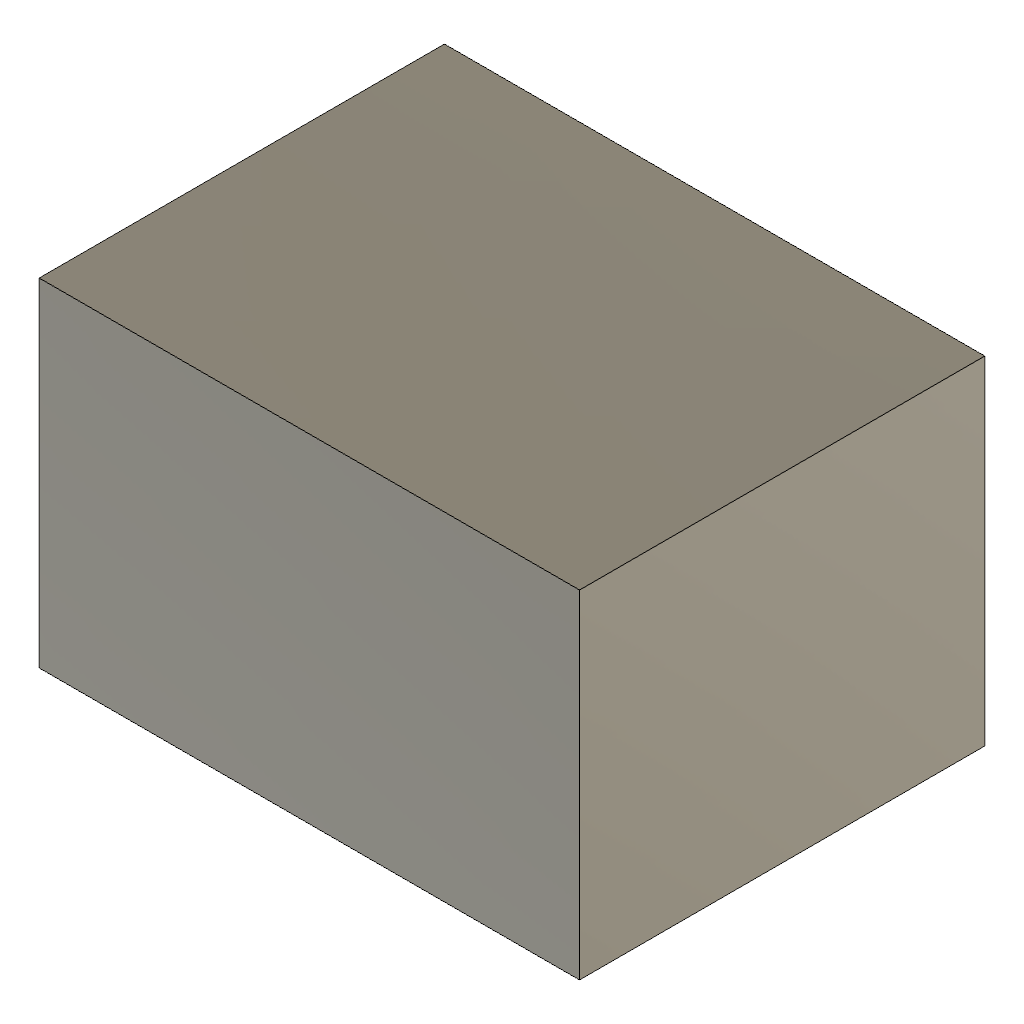
vendor_ExtrudeSlotCut (Autodesk Fusion 360 design; units mm, degrees)
Autodesk Fusion 360 part; units mm, degrees
sketch "Base sketch" plane through (0, 0, 0) normal (0, 0, 1) x (1, 0, 0)
  line L0 (0, 0) -> (40, 0)
  line L1 (40, 0) -> (40, 30)
  line L2 (40, 30) -> (0, 30)
  line L3 (0, 30) -> (0, 0)
extrude "Base extrude" add sketch "Base sketch" along normal blind 25
sketch "Slot sketch" plane through (0, 0, 0) normal (0, 0, 1) x (1, 0, 0)
  line L0 (15, 10) -> (25, 10)
  arc A0 (25, 10) -> (25, 20) centre (25, 15) ccw
  line L1 (25, 20) -> (15, 20)
  arc A1 (15, 20) -> (15, 10) centre (15, 15) ccw
extrude "Slot extrude" cut sketch "Slot sketch" along normal blind 20
equation "height = 20.0 mm"
